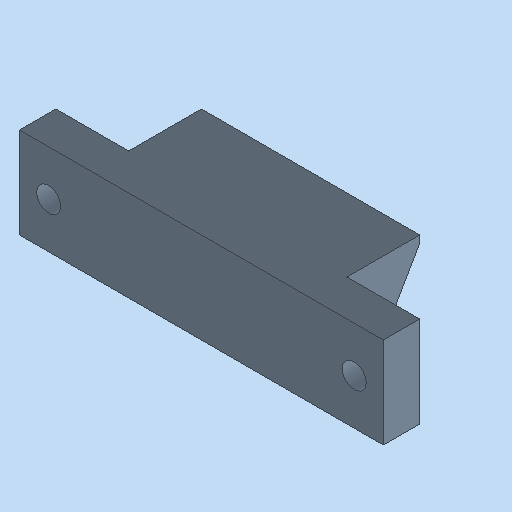
# Autodesk Inventor part: MM0948AN002_G01_117
Saved by Autodesk Inventor 2023.3 (Build 273359000, 359)
## iProperties
Created: 2023-09-27
Part Number: MM0948AN002_G01_117
Material: 1.4112 X90CrMoV18
Description: =<RBPARTNOTITLE2>
Document SubType Name: Modeling
Designer: RIC7AN
Mass: 346.586 g
Surface Area: 110.911 cm^2
Volume: 44.1511 cm^3
Density: 7.85 g/cm^3
Appearance: Stahl - kein Standard AnP
RBPARTMADEOF: 25 x 30 x 100 (FM)
RBDRAWINGMISSINGSPEC: --
AnP_Kategorie: 1
RBPARTNOTITLE2: Anfertigungsteil
RBSURFACE: --
RBPARTNOTITLE1: manufactured part
RBSURFACE2: --
AnP_Material: =<Material>
RBMATERIAL: =<Material>
RBMATNO: =<Part Number>
RBPARTNO: SIEHE MNR
MaxAbmaße: 25 x 30 x 100 (FM)
Author: RIC7AN
Keywords: =<RBPARTMADEOF>
Comments: =<RBSURFACE2>
Revision Number: 01
Autodesk Inventor part; units mm, degrees
ref_plane "YZ Plane" through (0, 0, 0) normal (1, 0, 0) x (0, 1, 0)
ref_plane "XZ Plane" through (0, 0, 0) normal (0, 1, 0) x (-1, 0, 0)
ref_plane "XY Plane" through (0, 0, 0) normal (0, 0, 1) x (1, 0, 0)
sketch "Skizze1" plane through (0, 0, 0) normal (0, 0, 1) x (1, 0, 0)
  line L0 (-50, 30) -> (50, 30)
  line L1 (50, 30) -> (50, 0)
  line L2 (50, 0) -> (-50, 0)
  line L3 (-50, 0) -> (-50, 30)
  line L4 (0, 36) -> (0, -6) projected
  line L5 (-70, 0) -> (70, 0) projected
  line L6 (-50, 30) -> (-30, 30)
  line L7 (-30, 30) -> (-30, 10)
  line L8 (-30, 10) -> (-50, 10)
  line L9 (-50, 10) -> (-50, 30)
  line L10 (50, 30) -> (30, 30)
  line L11 (30, 30) -> (30, 10)
  line L12 (30, 10) -> (50, 10)
  line L13 (50, 10) -> (50, 30)
  point P0 (0, 0)
  dimension "d0" = 100
  dimension "d1" = 30
  dimension "d4" = 20
  dimension "d5" = 10
  constraints: 24 end point, 6 parallel, 3 horizontal, 3 perpendicular, 2 collinear, 2 other
  measures "d0" distance of L0.start L0.end
  measures "d1" distance of L0.end L1.end
  measures "d4" distance of L7.end L8.end
  measures "d5" distance between parallel lines of L2 L8
extrude "Extrusion1" add sketch "Skizze1" along normal mid plane 25 contours L0 L4 L2 L3 L8 L7 | L0 L11 L12 L1 L2 L4
sketch "Skizze2" plane through (30, 10, 12.5) normal (1, 0, 0) x (0, 0, -1)
  line L0 (25, 20) -> (0, 20) projected
  line L1 (0, 0) -> (0, 20) projected
  line L2 (0, 0) -> (25, 0) projected
  line L3 (25, 20) -> (25, 0) projected
  line L4 (2, 20) -> (25, 6.7209)
  point P0 (12.5, -10)
  dimension "d6" = 30
  dimension "d7" = 2
  constraints: 2 end point, 2 point on line
  measures "d6" angle of L0 L4
  measures "d7" distance from line of L1 L4.start
extrude "Extrusion2" cut sketch "Skizze2" against normal through all contours L3 L4 L0
sketch "Skizze3" plane through (-30, 30, 10.5) normal (0, 0.8660254, -0.5) x (1, 0, 0)
  line L0 (30, 42.2487) -> (30, -9.0622) projected
  line L1 (60, 0) -> (0, 0) projected
  point P0 (30, 24.0933)
  point P1 (16.5, 11)
  point P2 (30, 11)
  point P3 (43.5, 11)
  dimension "d10" = 27
  dimension "d11" = 13.5
  dimension "d12" = 11
  constraints: 1 horizontal alignment, 1 symmetric about line
  measures "d10" distance of point (43.5, 11) point (16.5, 11)
  measures "d11" distance of point (30, 11) point (16.5, 11)
  measures "d12" distance from line of L1 point (16.5, 11)
hole "Bohrung1" at (-13.5, 24.5, 0.9737) at (0, 24.5, 0.9737) at (13.5, 24.5, 0.9737) direction (0, -0.8660254, 0.5) diameter 4.917 depth 17.1 tip angle 118 thread size "M6x1" designation "M6" class "6H" standard "ISO Metric profile"
sketch "Skizze4" plane through (-50, 10, 12.5) normal (0, 1, 0) x (1, 0, 0)
  line L0 (120, 12.5) -> (-20, 12.5) projected
  line L1 (50, 30) -> (50, -5) projected
  point P0 (50, 12.5)
  point P1 (8, 12.5)
  point P2 (92, 12.5)
  dimension "d20" = 84
  constraints: 2 point on line, 1 symmetric about line
  measures "d20" distance of point (92, 12.5) point (8, 12.5)
hole "Bohrung2" at (-42, 10, 0) at (42, 10, 0) direction (0, -1, 0) diameter 6.6 end through all clearance for "Inbusschraube ISO 4762  versenkt" size "M6" standard "ISO"
equation "\"d11\" = 0.5 * d10"
